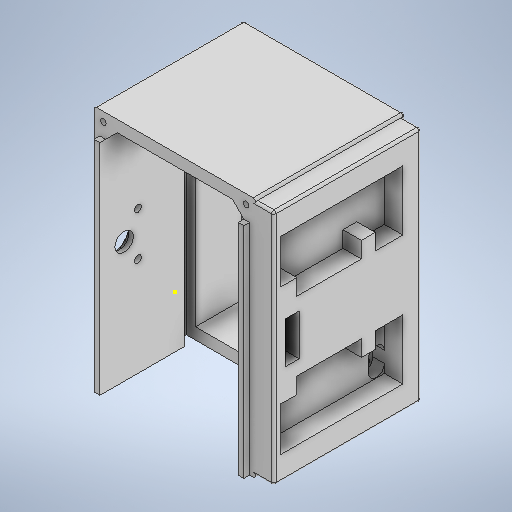
# Autodesk Inventor part: pudelkov2
Saved by Autodesk Inventor 2025.2 (Build 292293000, 293)
## iProperties
Created: 2026-10-25
Part Number: pudelkov2
Material: Generic
Document SubType Name: Modeling
Designer: Kacper
Density: 1 g/cm^3
Appearance: Default
Author: Kacper
Autodesk Inventor part; units mm, degrees
ref_plane "YZ Plane" through (0, 0, 0) normal (1, 0, 0) x (0, 1, 0)
sketch "Sketch1" plane through (0, 0, 0) normal (0, 0, 1) x (1, 0, 0)
  line L0 (-35, 52.5) -> (35, 52.5)
  line L1 (35, 52.5) -> (35, -52.5)
  line L2 (35, -52.5) -> (-35, -52.5)
  line L3 (-35, -52.5) -> (-35, 52.5)
  line L4 (-35, 52.5) -> (35, -52.5) construction
  line L5 (35, 52.5) -> (-35, -52.5) construction
  point P0 (0, 0)
  dimension "d0" = 105
  dimension "d1" = 70
  constraints: 12 end point, 2 midpoint, 2 parallel, 1 horizontal, 1 perpendicular
  measures "d0" distance between parallel lines of L2 L0
  measures "d1" distance between parallel lines of L1 L3
extrude "Extrusion1" add sketch "Sketch1" along normal blind 6
sketch "Sketch2" plane through (0, 0, 6) normal (0, 0, 1) x (1, 0, 0)
  line L0 (-35, -52.5) -> (35, -52.5) projected
  line L1 (35, -52.5) -> (35, 52.5) projected
  line L2 (35, 52.5) -> (-35, 52.5) projected
  line L3 (-35, 52.5) -> (-35, -52.5) projected
  line L4 (30, -47.5) -> (-30, -47.5)
  line L5 (-30, -47.5) -> (-30, 47.5)
  line L6 (-30, 47.5) -> (30, 47.5)
  line L7 (30, 47.5) -> (30, -47.5)
  line L8 (30, -47.5) -> (-30, 47.5) construction
  line L9 (-30, -47.5) -> (30, 47.5) construction
  point P0 (0, 0)
  dimension "d4" = 5
  dimension "d5" = 5
  constraints: 12 end point, 2 midpoint, 2 parallel, 1 horizontal, 1 perpendicular
  measures "d4" distance between parallel lines of L3 L5
  measures "d5" distance between parallel lines of L2 L6
extrude "Extrusion2" add sketch "Sketch2" along normal blind 20
sketch "Sketch3" plane through (0, 0, 6) normal (0, 0, 1) x (1, 0, 0)
  line L0 (24.5, -42.5) -> (-24.5, -42.5) construction
  line L1 (-24.5, -42.5) -> (-24.5, 15.5) construction
  line L2 (-24.5, 15.5) -> (24.5, 15.5) construction
  line L3 (24.5, 15.5) -> (24.5, -42.5) construction
  line L4 (-30, -47.5) -> (-30, 47.5) projected
  line L5 (30, -47.5) -> (-30, -47.5) projected
  circle A0 centre (24.5, -42.5) radius 1.1
  circle A1 centre (-24.5, -42.5) radius 1.1
  circle A2 centre (24.5, 15.5) radius 1.1
  circle A3 centre (-24.5, 15.5) radius 1.1
  point P0 (0, 0)
  dimension "d9" = 58
  dimension "d10" = 5.5
  dimension "d12" = 5
  dimension "d13" = 49
  dimension "d14" = 2.2
  dimension "d15" = 2.2
  dimension "d16" = 2.2
  dimension "d17" = 2.2
  constraints: 8 end point, 4 centre point, 4 coincident, 2 parallel, 1 horizontal, 1 perpendicular
  measures "d9" distance of L0.end L1.end
  measures "d10" distance between parallel lines of L1 L4
  measures "d12" distance between parallel lines of L5 L0
  measures "d13" distance of L0.start L0.end
  measures "d14" diameter of A0
  measures "d15" diameter of A1
  measures "d16" diameter of A2
  measures "d17" diameter of A3
extrude "Extrusion3" add sketch "Sketch3" along normal blind 6
sketch "Sketch4" plane through (30, -47.5, 6) normal (-1, 0, 0) x (0, 0, 1)
  line L0 (6, 3.9) -> (6, 6.1) projected
  line L1 (0, 6.1) -> (0, 3.9) projected
  line L2 (6, 61.9) -> (6, 64.1) projected
  line L3 (0, 64.1) -> (0, 61.9) projected
  line L4 (6.5, 18.7) -> (6.5, 6.7) construction
  line L5 (10, 15.2) -> (10, 10.2)
  line L6 (3, 10.2) -> (3, 15.2)
  arc A0 (10, 15.2) -> (3, 15.2) centre (6.5, 15.2) ccw
  arc A1 (3, 10.2) -> (10, 10.2) centre (6.5, 10.2) ccw
  line L7 (0, 0) -> (0, 95) projected
  point P0 (-6, 47.5)
  point P1 (6.5, 12.7)
  point P2 (6, 5)
  dimension "d20" = 7.7
  dimension "d21" = 12
  dimension "d22" = 7
  dimension "d23" = 3
  constraints: 8 end point, 8 point on circle, 4 tangent, 2 centre point, 2 midpoint, 2 point on line, 1 parallel, 1 vertical
  measures "d20" vertical distance of point (6, 5) point (6.5, 12.7)
  measures "d21" distance of point (6.5, 6.7) point (6.5, 18.7)
  measures "d22" distance between parallel lines of L5 L6
  measures "d23" distance between parallel lines of L6 L7
extrude "Extrusion4" cut sketch "Sketch4" against normal up to surface (5 mm away)
fillet "Fillet1" radius 1 8 edges at (-35, 52.5, 13) (-35, -52.5, 13) (35, 52.5, 13) (35, -52.5, 13) (35, 0, 0) (0, -52.5, 0) (-35, 0, 0) (0, 52.5, 0)
sketch "Sketch5" plane through (0, 0, 26) normal (0, 0, 1) x (1, 0, 0)
  line L0 (34, 52.5) -> (-34, 52.5) projected
  line L1 (-30, 47.5) -> (30, 47.5) projected
  line L2 (-35, 51.5) -> (-35, -51.5) projected
  line L3 (-30, -47.5) -> (-30, 47.5) projected
  line L4 (35, -51.5) -> (35, 51.5) projected
  line L5 (30, 47.5) -> (30, -47.5) projected
  arc A0 (35, 51.5) -> (34, 52.5) centre (34, 51.5) ccw projected
  arc A1 (-34, 52.5) -> (-35, 51.5) centre (-34, 51.5) ccw projected
  line L6 (30, -47.5) -> (-30, -47.5) projected
  line L7 (-34, -52.5) -> (34, -52.5) projected
  arc A2 (-35, -51.5) -> (-34, -52.5) centre (-34, -51.5) ccw projected
  arc A3 (34, -52.5) -> (35, -51.5) centre (34, -51.5) ccw projected
  line L8 (34, -51.5) -> (34, 51.5)
  line L9 (34, 51.5) -> (-34, 51.5)
  line L10 (-34, 51.5) -> (-34, -51.5)
  line L11 (34, -51.5) -> (34, -52.5)
  line L12 (-34, -51.5) -> (-34, -52.5)
  point P0 (0, 0)
  constraints: 10 end point, 2 parallel, 2 vertical, 1 perpendicular
extrude "Extrusion5" add sketch "Sketch5" along normal blind 5 contours A0 L4 A3 L11 L8 L9 L10 L12 A2 L2 A1 L0
sketch "Sketch6" plane through (0, 0, 31) normal (0, 0, 1) x (1, 0, 0)
  line L0 (-34, 51.5) -> (-34, -52.5) projected
  line L1 (-34, -52.5) -> (34, -52.5) projected
  line L2 (34, -52.5) -> (34, 51.5) projected
  line L3 (34, 51.5) -> (-34, 51.5) projected
  line L4 (30, -47.5) -> (-30, -47.5) projected
  line L5 (-30, -47.5) -> (-30, 47.5) projected
  line L6 (-30, 47.5) -> (30, 47.5) projected
  line L7 (30, 47.5) -> (30, -47.5) projected
  line L8 (34, 52.5) -> (-34, 52.5) projected
  line L9 (-35, 51.5) -> (-35, -51.5) projected
  arc A0 (-34, 52.5) -> (-35, 51.5) centre (-34, 51.5) ccw projected
  arc A1 (35, 51.5) -> (34, 52.5) centre (34, 51.5) ccw projected
  line L10 (35, -51.5) -> (35, 51.5) projected
  arc A2 (-35, -51.5) -> (-34, -52.5) centre (-34, -51.5) ccw projected
  arc A3 (34, -52.5) -> (35, -51.5) centre (34, -51.5) ccw projected
  line L11 (-30, -47.5) -> (-30, -52.5)
  line L12 (30, -47.5) -> (30, -52.5)
  point P0 (0, 0)
  constraints: 4 end point, 2 perpendicular, 2 point on line
extrude "Extrusion6" add sketch "Sketch6" along normal blind 5 contours L3 L2 L1 L12 L7 L6 L5 L11 L0 | L0 A2 L9 A0 L8 A1 L10 A3 L2 L3
sketch "Sketch7" plane through (0, 0, 36) normal (0, 0, 1) x (1, 0, 0)
  line L0 (-35, 51.5) -> (-35, -51.5) projected
  line L1 (-30, -52.5) -> (-30, 47.5) projected
  line L2 (-30, 47.5) -> (30, 47.5) projected
  line L3 (30, 47.5) -> (30, -52.5) projected
  line L4 (34, 52.5) -> (-34, 52.5) projected
  arc A0 (-34, 52.5) -> (-35, 51.5) centre (-34, 51.5) ccw projected
  arc A1 (35, 51.5) -> (34, 52.5) centre (34, 51.5) ccw projected
  line L5 (35, -51.5) -> (35, 51.5) projected
  arc A2 (34, -52.5) -> (35, -51.5) centre (34, -51.5) ccw projected
  line L6 (30, -52.5) -> (34, -52.5) projected
  line L7 (-34, -52.5) -> (-30, -52.5) projected
  arc A3 (-35, -51.5) -> (-34, -52.5) centre (-34, -51.5) ccw projected
  point P0 (0, 0)
extrude "Extrusion7" add sketch "Sketch7" along normal blind 29
sketch "Sketch9" plane through (-35, -51.5, 1) normal (-1, 0, 0) x (0, 0, 1)
  line L0 (0, 103) -> (64, 103) projected
  line L1 (0, 0) -> (0, 103) projected
  line L2 (64, 0) -> (0, 0) projected
  line L3 (64, 103) -> (64, 0) projected
  line L4 (64, 104) -> (0, 104) projected
  line L5 (30, -1) -> (64, -1) projected
  line L6 (64, -1) -> (64, 0) projected
  line L7 (64, 103) -> (64, 104) projected
  arc A0 (-1, 0) -> (0, -1) centre (0, 0) ccw projected
  line L8 (-1, 103) -> (-1, 0) projected
  line L9 (0, -1) -> (25, -1) projected
  line L10 (25, -1) -> (30, -1) projected
  line L11 (0, 104) -> (0, 103) projected
  arc A1 (0, 104) -> (-1, 103) centre (0, 103) ccw projected
  line L12 (0, 103) -> (-1, 103) projected
  point P0 (-1, 51.5)
  point P1 (56, 51.5)
  dimension "d33" = 52.5
  dimension "d35" = 8
  measures "d33" distance from line of L5 point (56, 51.5)
  measures "d35" distance from line of L3 point (56, 51.5)
hole "Hole1" at (-35, 0, 57) direction (1, 0, 0) diameter 8 depth 5 countersink diameter 14 countersink angle 90
sketch "Sketch10" plane through (-35, -51.5, 1) normal (-1, 0, 0) x (0, 0, 1)
  circle A0 centre (56, 51.5) radius 4 projected
  circle A1 centre (56, 51.5) radius 7 projected
  circle A2 centre (56, 51.5) radius 7 projected
  line L0 (0, 103) -> (64, 103) projected
  line L1 (0, 0) -> (0, 103) projected
  line L2 (64, 0) -> (0, 0) projected
  line L3 (64, 103) -> (64, 0) projected
  point P0 (-1, 51.5)
  point P1 (50, 61)
  point P2 (50, 42)
  dimension "d47" = 9.5
  dimension "d48" = 9.5
  dimension "d49" = 14
  dimension "d50" = 14
  measures "d47" vertical distance of point (50, 42) A0.centre
  measures "d48" vertical distance of point (50, 61) A0.centre
  measures "d49" distance from line of L3 point (50, 42)
  measures "d50" distance from line of L3 point (50, 61)
hole "Hole2" at (-35, 9.5, 51) at (-35, -9.5, 51) direction (1, 0, 0) diameter 3 depth 5 countersink diameter 5 countersink angle 90
sketch "Sketch14" plane through (0, 0, 65) normal (0, 0, 1) x (1, 0, 0)
  arc A0 (-35, -51.5) -> (-34, -52.5) centre (-34, -51.5) ccw projected
  line L0 (-34, -52.5) -> (-30, -52.5) projected
  line L1 (-30, -52.5) -> (-30, 47.5) projected
  line L2 (-30, 47.5) -> (30, 47.5) projected
  line L3 (30, 47.5) -> (30, -52.5) projected
  line L4 (30, -52.5) -> (34, -52.5) projected
  arc A1 (34, -52.5) -> (35, -51.5) centre (34, -51.5) ccw projected
  line L5 (35, -51.5) -> (35, 51.5) projected
  arc A2 (35, 51.5) -> (34, 52.5) centre (34, 51.5) ccw projected
  line L6 (34, 52.5) -> (-34, 52.5) projected
  arc A3 (-34, 52.5) -> (-35, 51.5) centre (-34, 51.5) ccw projected
  line L7 (-35, 51.5) -> (-35, -51.5) projected
  point P0 (0, 0)
  point P1 (25, 47.5)
  point P2 (30, 42.5)
  point P3 (-30, 42.5)
  point P4 (-25, 47.5)
  dimension "d83" = 5
  dimension "d84" = 5
  dimension "d85" = 5
  dimension "d86" = 5
  constraints: 4 point on line
  measures "d83" distance of L2.end point (30, 42.5)
  measures "d84" distance of L2.end point (25, 47.5)
  measures "d85" distance of point (-30, 42.5) L1.end
  measures "d86" horizontal distance of point (-25, 47.5) point (-30, 42.5)
sketch "Sketch15" plane through (-30, 47.5, 31) normal (0, -1, 0) x (1, 0, 0)
  line L0 (60, 0) -> (60, 34) projected
  line L1 (0, 0) -> (0, 34) projected
  point P0 (30, -31)
  point P1 (60, 22)
  point P2 (0, 22)
  dimension "d87" = 12
  dimension "d88" = 12
  constraints: 2 point on line
  measures "d87" distance of L0.end point (60, 22)
  measures "d88" distance of L1.end point (0, 22)
ref_plane "Work Plane4" through (-25, 47.5, 65) normal (0.6782801, -0.6782801, -0.2826167) x (-0.7071068, -0.7071068, 0)
ref_plane "Work Plane5" through (25, 47.5, 65) normal (0.6782801, 0.6782801, 0.2826167) x (0.7071068, -0.7071068, 0)
sketch "Sketch20" plane through (-25, 47.5, 65) normal (0.6782801, -0.6782801, -0.2826167) x (-0.7071068, -0.7071068, 0)
  line L0 (7.0711, 0) -> (0, 0)
  line L1 (0, 0) -> (3.5355, 12.51)
  line L2 (3.5355, 12.51) -> (7.0711, 0)
  point P0 (15.9099, 47.8617)
  constraints: 6 end point, 1 horizontal
sketch "Sketch21" plane through (25, 47.5, 65) normal (0.6782801, 0.6782801, 0.2826167) x (0.7071068, -0.7071068, 0)
  line L0 (0, 0) -> (7.0711, 0)
  line L1 (7.0711, 0) -> (3.5355, 12.51)
  line L2 (3.5355, 12.51) -> (0, 0)
  point P0 (15.9099, 47.8617)
  constraints: 6 end point, 1 horizontal
extrude "Extrusion9" add sketch "Sketch21" along normal blind 3.5
extrude "Extrusion10" add sketch "Sketch20" against normal blind 3.5
sketch "Sketch23" plane through (0, 0, 65) normal (0, 0, 1) x (1, 0, 0)
  line L0 (-30, 42.5) -> (-32.374, 45.2861) projected
  line L1 (-32.374, 45.2861) -> (-27.7861, 49.874) projected
  line L2 (-27.7861, 49.874) -> (-25, 47.5) projected
  line L3 (-25, 47.5) -> (25, 47.5) projected
  line L4 (25, 47.5) -> (27.7861, 49.874) projected
  line L5 (27.7861, 49.874) -> (32.374, 45.2861) projected
  line L6 (32.374, 45.2861) -> (30, 42.5) projected
  line L7 (30, 42.5) -> (30, -52.5) projected
  line L8 (30, -52.5) -> (34, -52.5) projected
  arc A0 (34, -52.5) -> (35, -51.5) centre (34, -51.5) ccw projected
  line L9 (35, -51.5) -> (35, 51.5) projected
  arc A1 (35, 51.5) -> (34, 52.5) centre (34, 51.5) ccw projected
  line L10 (34, 52.5) -> (-34, 52.5) projected
  arc A2 (-34, 52.5) -> (-35, 51.5) centre (-34, 51.5) ccw projected
  line L11 (-35, 51.5) -> (-35, -51.5) projected
  arc A3 (-35, -51.5) -> (-34, -52.5) centre (-34, -51.5) ccw projected
  line L12 (-34, -52.5) -> (-30, -52.5) projected
  line L13 (-30, -52.5) -> (-30, 42.5) projected
  line L14 (-35, 42.5) -> (-35, 52.5)
  line L15 (35, 42.5) -> (35, 52.5)
  line L16 (35, 52.5) -> (-35, 52.5)
  line L17 (34, 52.5) -> (-34, 52.5) projected
  line L18 (-35, 38) -> (35, 38)
  line L19 (-35, 38) -> (-35, 52.5)
  line L20 (35, 40.6441) -> (35, 52.5)
  point P0 (0, 0)
  dimension "d99" = 4.5
  constraints: 12 end point, 8 point on line, 2 parallel, 1 collinear, 1 perpendicular, 1 vertical
  measures "d99" distance from line of L18 L0.start
extrude "Extrusion12" cut sketch "Sketch23" along normal blind 5 contours L13 L18 L11 A2 L10 A1 L9 L7 L6 L5 L4 L3 L2 L1 L0 | L0 L1 L2 L3 L4 L5 L6 L7 L18 L13
sketch "Sketch24" plane through (0, 0, 65) normal (0, 0, 1) x (1, 0, 0)
  point P0 (0, 0)
sketch "Sketch25" plane through (0, 0, 65) normal (0, 0, 1) x (1, 0, 0)
  line L0 (-25, 47.5) -> (-30, 42.5) projected
  line L1 (-25, 47.5) -> (25, 47.5) projected
  line L2 (25, 47.5) -> (30, 42.5) projected
  line L3 (30, 42.5) -> (30, -52.5) projected
  line L4 (30, -52.5) -> (34, -52.5) projected
  arc A0 (34, -52.5) -> (35, -51.5) centre (34, -51.5) ccw projected
  line L5 (35, -51.5) -> (35, 51.5) projected
  arc A1 (35, 51.5) -> (34, 52.5) centre (34, 51.5) ccw projected
  line L6 (34, 52.5) -> (-34, 52.5) projected
  arc A2 (-34, 52.5) -> (-35, 51.5) centre (-34, 51.5) ccw projected
  line L7 (-35, 51.5) -> (-35, -51.5) projected
  arc A3 (-35, -51.5) -> (-34, -52.5) centre (-34, -51.5) ccw projected
  line L8 (-34, -52.5) -> (-30, -52.5) projected
  line L9 (-30, -52.5) -> (-30, 42.5) projected
  point P0 (0, 0)
  point P1 (-31, 48.5)
  point P2 (31, 48.5)
  dimension "d100" = 4
  dimension "d101" = 4
  dimension "d102" = 4
  dimension "d103" = 4
  measures "d100" distance from line of L6 point (-31, 48.5)
  measures "d101" distance from line of L7 point (-31, 48.5)
  measures "d102" distance from line of L6 point (31, 48.5)
  measures "d103" distance from line of L5 point (31, 48.5)
hole "Hole6" at (-31, 48.5, 65) at (31, 48.5, 65) direction (0, 0, -1) diameter 2.459 depth 8.1 tip angle 118 thread size "M3x0.5" class "6H" standard "ISO Metric profile"
sketch "Sketch26" plane through (0, 0, 65) normal (0, 0, 1) x (1, 0, 0)
  circle A0 centre (31, 48.5) radius 1.2295 projected
  circle A1 centre (-31, 48.5) radius 1.2295 projected
  line L0 (-25, 47.5) -> (-30, 42.5) projected
  line L1 (-25, 47.5) -> (25, 47.5) projected
  line L2 (25, 47.5) -> (30, 42.5) projected
  line L3 (30, 42.5) -> (30, -52.5) projected
  line L4 (30, -52.5) -> (34, -52.5) projected
  arc A2 (34, -52.5) -> (35, -51.5) centre (34, -51.5) ccw projected
  line L5 (35, -51.5) -> (35, 51.5) projected
  arc A3 (35, 51.5) -> (34, 52.5) centre (34, 51.5) ccw projected
  line L6 (34, 52.5) -> (-34, 52.5) projected
  arc A4 (-34, 52.5) -> (-35, 51.5) centre (-34, 51.5) ccw projected
  line L7 (-35, 51.5) -> (-35, -51.5) projected
  arc A5 (-35, -51.5) -> (-34, -52.5) centre (-34, -51.5) ccw projected
  line L8 (-34, -52.5) -> (-30, -52.5) projected
  line L9 (-30, -52.5) -> (-30, 42.5) projected
  line L10 (30, -47.5) -> (-30, -47.5) projected
  line L11 (-30, -52.5) -> (-32.5, -52.5)
  line L12 (-32.5, -52.5) -> (-32.5, 42.5)
  line L13 (-32.5, 42.5) -> (-30, 42.5)
  line L14 (-30, 42.5) -> (-30, -52.5)
  line L15 (30, 42.5) -> (32.5, 42.5)
  line L16 (32.5, 42.5) -> (32.5, -52.5)
  line L17 (32.5, -52.5) -> (30, -52.5)
  line L18 (30, -52.5) -> (30, 42.5)
  point P0 (0, 0)
  dimension "d115" = 2.5
  dimension "d116" = 2.5
  constraints: 16 end point, 4 parallel, 2 horizontal, 2 perpendicular, 1 point on line
  measures "d115" distance between parallel lines of L12 L9
  measures "d116" distance between parallel lines of L16 L3
extrude "Extrusion13" add sketch "Sketch26" along normal blind 2.5 contours L9 L8 L12 L13 | L15 L16 L4 L3
sketch "Sketch27" plane through (-34, -52.5, 1) normal (0, -1, 0) x (1, 0, 0)
  line L0 (0, 0) -> (0, 25) projected
  line L1 (68, 0) -> (0, 0) projected
  line L2 (68, 25) -> (68, 0) projected
  line L3 (0, 25) -> (68, 25) projected
  line L4 (0, -1) -> (68, -1) projected
  line L5 (69, 0) -> (69, 64) projected
  line L6 (-1, 64) -> (-1, 0) projected
  point P0 (34, -1)
  point P1 (34, 2)
  dimension "d117" = 35
  dimension "d118" = 3
  measures "d117" distance from line of L5 point (34, 2)
  measures "d118" distance from line of point (34, 2) L4
hole "Hole7" at (0, -52.5, 3) direction (0, 1, 0) diameter 2.459 depth 17 tip angle 118 thread size "M3x0.5" class "6H" standard "ISO Metric profile"
sketch "Sketch30" plane through (35, -51.5, 1) normal (1, 0, 0) x (0, 0, -1)
  line L0 (-64, 103) -> (0, 103) projected
  line L1 (-64, 0) -> (-64, 103) projected
  line L2 (0, 0) -> (-64, 0) projected
  line L3 (0, 103) -> (0, 0) projected
  arc A0 (-15, 14.2) -> (-8, 14.2) centre (-11.5, 14.2) ccw projected
  line L4 (-15, 14.2) -> (-15, 19.2) projected
  arc A1 (-8, 19.2) -> (-15, 19.2) centre (-11.5, 19.2) ccw projected
  line L5 (-8, 19.2) -> (-8, 14.2) projected
  line L6 (-64, 0) -> (-15, 0)
  line L7 (-15, 0) -> (-15, 103)
  line L8 (-15, 103) -> (-64, 103)
  line L9 (-64, 103) -> (-64, 0)
  line L10 (0, 0) -> (-64, 0) projected
  line L11 (-64, 103) -> (0, 103) projected
  line L12 (-64, 0) -> (-64, 103) projected
  point P0 (1, 51.5)
  point P1 (-15, 0)
  constraints: 8 end point, 4 collinear, 2 parallel, 1 horizontal, 1 perpendicular
extrude "Extrusion14" add sketch "Sketch30" along normal blind 8 contours L0 L7 L4 L2 L1
sketch "Sketch31" plane through (43, -51.5, 1) normal (1, 0, 0) x (0, 0, -1)
  line L0 (-15, 103) -> (-64, 103) projected
  line L1 (-64, 103) -> (-64, 0) projected
  line L2 (-64, 0) -> (-15, 0) projected
  line L3 (-15, 0) -> (-15, 103) projected
  line L4 (-59, 42.5) -> (-53, 42.5)
  line L5 (-53, 42.5) -> (-53, 60.5)
  line L6 (-53, 60.5) -> (-59, 60.5)
  line L7 (-59, 60.5) -> (-59, 42.5)
  line L8 (-54, 66.5) -> (-54, 73.5)
  line L9 (-54, 73.5) -> (-61, 73.5)
  line L10 (-61, 73.5) -> (-61, 92.5)
  line L11 (-26, 66.5) -> (-26, 73.5)
  line L12 (-26, 73.5) -> (-20, 73.5)
  line L13 (-20, 73.5) -> (-20, 66.5)
  line L14 (-26, 66.5) -> (-54, 66.5)
  line L15 (-20, 66.5) -> (-15, 66.5)
  line L16 (-61, 92.5) -> (-15, 92.5)
  line L17 (-15, 0) -> (-15, 103) projected
  line L18 (-64, 51.5) -> (-15, 51.5) construction
  line L19 (-54, 36.5) -> (-54, 29.5)
  line L20 (-54, 29.5) -> (-61, 29.5)
  line L21 (-61, 29.5) -> (-61, 10.5)
  line L22 (-26, 36.5) -> (-26, 29.5)
  line L23 (-26, 29.5) -> (-20, 29.5)
  line L24 (-20, 29.5) -> (-20, 36.5)
  line L25 (-26, 36.5) -> (-54, 36.5)
  line L26 (-20, 36.5) -> (-15, 36.5)
  line L27 (-61, 10.5) -> (-15, 10.5)
  point P0 (1, 51.5)
  point P1 (-54, 70)
  point P2 (-15, 10.5)
  dimension "d140" = 18
  dimension "d141" = 6
  dimension "d142" = 42.5
  dimension "d144" = 5
  dimension "d145" = 2
  dimension "d146" = 7
  dimension "d147" = 7
  dimension "d148" = 19
  dimension "d150" = 6
  dimension "d151" = 28
  dimension "d154" = 13
  constraints: 46 end point, 10 symmetric about line, 7 point on line, 6 perpendicular, 3 horizontal, 3 midpoint, 2 parallel, 1 collinear, 1 vertical
  measures "d140" distance of L4.end L5.end
  measures "d141" distance of L5.end L6.end
  measures "d142" distance between parallel lines of L0 L6
  measures "d144" distance between parallel lines of L1 L7
  measures "d145" distance between parallel lines of L10 L7
  measures "d146" distance of L8.start L8.end
  measures "d147" distance of L8.end L9.end
  measures "d148" distance of L9.end L10.end
  measures "d150" distance of L11.end L12.end
  measures "d151" distance of L11.start L8.start
  measures "d154" distance between parallel lines of L6 L9
extrude "Extrusion15" cut sketch "Sketch31" against normal up to surface (8 mm away) contours L3 L15 L13 L12 L11 L14 L8 L9 L10 L16 | L3 L27 L21 L20 L19 L25 L22 L23 L24 L26 | L7 L6 L5 L4
sketch "Sketch32" plane through (35, -51.5, 1) normal (1, 0, 0) x (0, 0, -1)
  line L0 (-53, 60.5) -> (-53, 42.5) projected
  line L1 (-53, 42.5) -> (-59, 42.5) projected
  line L2 (-59, 42.5) -> (-59, 60.5) projected
  line L3 (-59, 60.5) -> (-53, 60.5) projected
  line L4 (-15, 66.5) -> (-20, 66.5) projected
  line L5 (-20, 66.5) -> (-20, 73.5) projected
  line L6 (-20, 73.5) -> (-26, 73.5) projected
  line L7 (-26, 73.5) -> (-26, 66.5) projected
  line L8 (-26, 66.5) -> (-54, 66.5) projected
  line L9 (-54, 66.5) -> (-54, 73.5) projected
  line L10 (-54, 73.5) -> (-61, 73.5) projected
  line L11 (-61, 73.5) -> (-61, 92.5) projected
  line L12 (-61, 92.5) -> (-15, 92.5) projected
  line L13 (-15, 92.5) -> (-15, 103) projected
  line L14 (-15, 103) -> (-64, 103) projected
  line L15 (-64, 103) -> (-64, 0) projected
  line L16 (-64, 0) -> (-15, 0) projected
  line L17 (-15, 0) -> (-15, 10.5) projected
  line L18 (-15, 10.5) -> (-61, 10.5) projected
  line L19 (-61, 10.5) -> (-61, 29.5) projected
  line L20 (-61, 29.5) -> (-54, 29.5) projected
  line L21 (-54, 29.5) -> (-54, 36.5) projected
  line L22 (-54, 36.5) -> (-26, 36.5) projected
  line L23 (-26, 36.5) -> (-26, 29.5) projected
  line L24 (-26, 29.5) -> (-20, 29.5) projected
  line L25 (-20, 29.5) -> (-20, 36.5) projected
  line L26 (-20, 36.5) -> (-15, 36.5) projected
  line L27 (-15, 36.5) -> (-15, 66.5) projected
  arc A0 (-8, 19.2) -> (-15, 19.2) centre (-11.5, 19.2) ccw projected
  line L28 (-8, 19.2) -> (-8, 14.2) projected
  arc A1 (-15, 14.2) -> (-8, 14.2) centre (-11.5, 14.2) ccw projected
  line L29 (-15, 19.2) -> (-15, 14.2) projected
  line L30 (-20, 36.5) -> (-15, 36.5) projected
  line L31 (-20, 29.5) -> (-20, 36.5) projected
  line L32 (-26, 29.5) -> (-20, 29.5) projected
  line L33 (-26, 36.5) -> (-26, 29.5) projected
  line L34 (-54, 36.5) -> (-26, 36.5) projected
  line L35 (-54, 29.5) -> (-54, 36.5) projected
  line L36 (-61, 29.5) -> (-54, 29.5) projected
  line L37 (-61, 10.5) -> (-61, 29.5) projected
  line L38 (-15, 10.5) -> (-61, 10.5) projected
  line L39 (-15, 10.5) -> (-15, 0) projected
  line L40 (0, 0) -> (-15, 0) projected
  line L41 (0, 103) -> (0, 0) projected
  line L42 (-15, 103) -> (0, 103) projected
  line L43 (-15, 103) -> (-15, 92.5) projected
  line L44 (-61, 92.5) -> (-15, 92.5) projected
  line L45 (-61, 73.5) -> (-61, 92.5) projected
  line L46 (-54, 73.5) -> (-61, 73.5) projected
  line L47 (-54, 66.5) -> (-54, 73.5) projected
  line L48 (-26, 66.5) -> (-54, 66.5) projected
  line L49 (-26, 73.5) -> (-26, 66.5) projected
  line L50 (-20, 73.5) -> (-26, 73.5) projected
  line L51 (-20, 66.5) -> (-20, 73.5) projected
  line L52 (-15, 66.5) -> (-20, 66.5) projected
  line L53 (-15, 66.5) -> (-15, 36.5) projected
  line L54 (-15, 10.5) -> (-8, 10.5)
  line L55 (-8, 92.5) -> (-15, 92.5)
  line L56 (-15, 36.5) -> (-8, 36.5)
  line L57 (-15, 66.5) -> (-8, 66.5)
  line L58 (-8, 10.5) -> (-8, 36.5)
  line L59 (-8, 66.5) -> (-8, 92.5)
  line L60 (-8, 19.2) -> (-8, 14.2) projected
  point P0 (1, 51.5)
  point P1 (-15, 92.5)
  constraints: 12 end point, 2 collinear, 2 equal length, 2 horizontal, 1 perpendicular, 1 vertical
extrude "Extrusion16" add sketch "Sketch32" along normal up to surface (8 mm away) contours L57 L59 L55 L13 L42 L41 L40 L17 L54 L58 L28 L56 L27
fillet "Fillet2" radius 1 8 edges at (39, -51.5, 1) (43, -51.5, 33) (43, 0, 1) (43, 0, 65) (39, -51.5, 65) (43, 51.5, 33) (39, 51.5, 1) (39, 51.5, 65)
body "Solid1"
